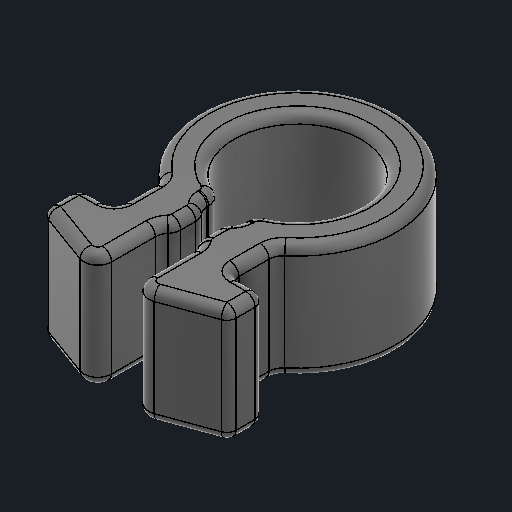
# Autodesk Inventor part: CableClip (ID3.2mm)
Saved by Autodesk Inventor 2026.2 (Build 302298000, 298)
## iProperties
Created: 2026-10-26
Part Number: CableClip (ID3.2mm)
Material: ABS Plastic
Document SubType Name: Modeling
Designer: JoshuaEah
Density: 1.06 g/cm^3
Appearance: Smooth - Black
Author: JoshuaEah
Autodesk Inventor part; units mm, degrees
ref_plane "YZ Plane" through (0, 0, 0) normal (1, 0, 0) x (0, 1, 0)
ref_plane "XZ Plane" through (0, 0, 0) normal (0, 1, 0) x (-1, 0, 0)
ref_plane "XY Plane" through (0, 0, 0) normal (0, 0, 1) x (1, 0, 0)
sketch "Sketch1" plane through (0, 0, 0) normal (0, 1, 0) x (-1, 0, 0)
  circle A0 centre (0, 0) radius 2.75
  line L0 (0, -2.75) -> (0, 2.75)
  line L1 (2.5, 3.436932) -> (2.5, 5.436932)
  line L2 (2.5, 5.436932) -> (4, 5.436932)
  line L3 (4, 5.436932) -> (4, 6.936932)
  line L4 (4, 6.936932) -> (0.8, 8.101637)
  line L5 (0.8, 4.831064) -> (0.8, 8.101637)
  line L6 (0.8, 4.831064) -> (0.5, 4.831064)
  line L7 (0.5, 4.831064) -> (0.5, 3.631064)
  line L8 (0.5, 3.631064) -> (0.8, 3.631064)
  circle A1 centre (0, 0) radius 4.25
  line L9 (0.8, 2.631064) -> (0.8, 3.631064)
  line L10 (-2.5, 3.436932) -> (-2.5, 5.436932)
  line L11 (-2.5, 5.436932) -> (-4, 5.436932)
  line L12 (-4, 5.436932) -> (-4, 6.936932)
  line L13 (-4, 6.936932) -> (-0.8, 8.101637)
  line L14 (-0.8, 4.831064) -> (-0.8, 8.101637)
  line L15 (-0.8, 4.831064) -> (-0.5, 4.831064)
  line L16 (-0.5, 4.831064) -> (-0.5, 3.631064)
  line L17 (-0.5, 3.631064) -> (-0.8, 3.631064)
  line L18 (-0.8, 2.631064) -> (-0.8, 3.631064)
  point P0 (-0.8, 2.631064)
  dimension "d0" = 5.5
  dimension "d1" = 8
  dimension "d2" = 5
  dimension "d3" = 1.2
  dimension "d4" = 0.3
  dimension "d5" = 1.5
  dimension "d7" = 1
  dimension "d8" = 2
  dimension "d9" = 110
  dimension "d10" = 1.5
  dimension "d11" = 1
  constraints: 38 end point, 10 symmetric about line, 4 perpendicular, 4 vertical, 3 point on circle, 1 centre point, 1 coincident, 1 collinear, 1 horizontal, 1 midpoint, 3 other
  measures "d0" diameter of A0
  measures "d1" diameter of L3 L0
  measures "d2" diameter of L1 L0
  measures "d3" distance of L6.end L7.end
  measures "d4" distance of L5.start L6.end
  measures "d7" diameter of L7 L0
  measures "d8" distance of L1.end L1.start
  measures "d9" angle of L3 L4
  measures "d10" distance of L2.end L3.end
  measures "d11" distance of L9.start L8.end
extrude "Extrusion1" add sketch "Sketch1" along normal blind 5 contours A0 L9 L8 L7 A1 L16 L17 L18 | L7 L6 L5 L4 L3 L2 L1 A1 | A1 L10 L11 L12 L13 L14 L15 L16 picked at (3.686343, -0.541007)
fillet "Fillet1" radius 0.6 14 edges at (-0.8, 2.5, 3.6311) (-0.8, 2.5, 2.6311) (0.8, 2.5, 2.6311) (0.8, 2.5, 3.6311) (0.8, 2.5, 4.8311) (-0.8, 2.5, 4.8311) (-0.5, 2.5, 4.8311) (0.5, 2.5, 4.8311) (-0.5, 2.5, 3.6311) (0.5, 2.5, 3.6311) (-0.8, 2.5, 8.1016) (0.8, 2.5, 8.1016) (2.5, 2.5, 3.4369) (-2.5, 2.5, 3.4369)
fillet "Fillet1" radius 0.4 6 edges at (-4, 2.5, 6.9369) (-4, 2.5, 5.4369) (4, 2.5, 6.9369) (4, 2.5, 5.4369) (-2.5, 2.5, 5.4369) (2.5, 2.5, 5.4369)
fillet "Fillet2" radius 0.4 72 edges at (-0.7612, 5, 5.1385) (-0.8, 5, 6.2977) (-1.0559, 5, 7.7362) (-2.671, 5, 7.4206) (-3.9277, 5, 6.8863) (-4, 5, 6.2469) (-3.8828, 5, 5.5541) (-3.25, 5, 5.4369) (-2.6172, 5, 5.3198) (-2.5, 5, 4.3834) (-2.5568, 5, 3.4751) (0, 5, -4.25) (2.5568, 5, 3.4751) (2.5, 5, 4.3834) (2.6172, 5, 5.3198) (3.25, 5, 5.4369) (3.8828, 5, 5.5541) (4, 5, 6.2469) (3.9277, 5, 6.8863) (2.671, 5, 7.4206) (1.0559, 5, 7.7362) (0.8, 5, 6.2977) (0.7612, 5, 5.1385) (0.5388, 5, 4.7691) (0.5, 5, 4.2311) (0.5388, 5, 3.693) (0.7612, 5, 3.3236) (0.8, 5, 3.0774) (0.8948, 5, 2.7197) (0, 5, -2.75) (-0.8948, 5, 2.7197) (-0.8, 5, 3.0774) (-0.7612, 5, 3.3236) (-0.5388, 5, 3.693) (-0.5, 5, 4.2311) (-0.5388, 5, 4.7691) (-0.5, 0, 4.2311) (-0.5388, 0, 3.693) (-0.7612, 0, 3.3236) (-0.8, 0, 3.0774) (-0.8948, 0, 2.7197) (0, 0, -2.75) (0.8948, 0, 2.7197) (0.8, 0, 3.0774) (0.7612, 0, 3.3236) (0.5388, 0, 3.693) (0.5, 0, 4.2311) (0.5388, 0, 4.7691) (0.7612, 0, 5.1385) (0.8, 0, 6.2977) (1.0559, 0, 7.7362) (2.671, 0, 7.4206) (3.9277, 0, 6.8863) (4, 0, 6.2469) (3.8828, 0, 5.5541) (3.25, 0, 5.4369) (2.6172, 0, 5.3198) (2.5, 0, 4.3834) (2.5568, 0, 3.4751) (0, 0, -4.25) (-2.5568, 0, 3.4751) (-2.5, 0, 4.3834) (-2.6172, 0, 5.3198) (-3.25, 0, 5.4369) (-3.8828, 0, 5.5541) (-4, 0, 6.2469) (-3.9277, 0, 6.8863) (-2.671, 0, 7.4206) (-1.0559, 0, 7.7362) (-0.8, 0, 6.2977) (-0.7612, 0, 5.1385) (-0.5388, 0, 4.7691)
body "Solid1"
